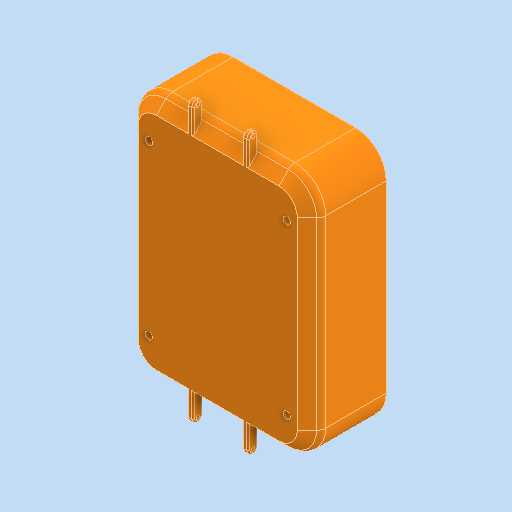
# Autodesk Inventor part: Cover Bawah
Saved by Autodesk Inventor 2026.2 (Build 302298010, 298A)
## iProperties
Created: 2026-05-23
Part Number: Cover Bawah
Material: PAEK Plastic
Document SubType Name: Modeling
Designer: HYLMI ATHA N
Density: 1.32 g/cm^3
Appearance: Orange
Author: HYLMI ATHA N
Autodesk Inventor part; units mm, degrees
(part 1 of 2)
ref_plane "XZ Plane" through (0, 0, 0) normal (0, 1, 0) x (-1, 0, 0)
ref_plane "XY Plane" through (0, 0, 0) normal (0, 0, 1) x (1, 0, 0)
sketch "Sketch2" plane through (0, 0, 0) normal (0, 0, 1) x (1, 0, 0)
  arc A0 (22.147, -28.6469) -> (23.335, -28.3619) centre (22.5, -27.5) ccw projected
  arc A1 (21.3819, -27.0644) -> (22.147, -28.6469) centre (21.59, -27.94) ccw projected
  arc A2 (23.6553, -27.1754) -> (21.3819, -27.0644) centre (22.5, -27.5) ccw projected
  arc A3 (25, -27.7096) -> (23.6553, -27.1754) centre (24.13, -27.94) ccw projected
  line L0 (25, -27.7096) -> (25, -25.6304) projected
  arc A4 (25, -25.1696) -> (25, -25.6304) centre (24.13, -25.4) ccw projected
  line L1 (25, -25.1696) -> (25, -23.0904) projected
  arc A5 (25, -22.6296) -> (25, -23.0904) centre (24.13, -22.86) ccw projected
  line L2 (25, -22.6296) -> (25, -20.5504) projected
  arc A6 (25, -20.0896) -> (25, -20.5504) centre (24.13, -20.32) ccw projected
  line L3 (25, -20.0896) -> (25, -18.0104) projected
  arc A7 (25, -17.5496) -> (25, -18.0104) centre (24.13, -17.78) ccw projected
  line L4 (25, -17.5496) -> (25, -15.4704) projected
  arc A8 (25, -15.0096) -> (25, -15.4704) centre (24.13, -15.24) ccw projected
  line L5 (25, -15.0096) -> (25, -12.9304) projected
  arc A9 (25, -12.4696) -> (25, -12.9304) centre (24.13, -12.7) ccw projected
  line L6 (25, -12.4696) -> (25, -10.3904) projected
  arc A10 (25, -9.9296) -> (25, -10.3904) centre (24.13, -10.16) ccw projected
  line L7 (25, -9.9296) -> (25, -7.8504) projected
  arc A11 (25, -7.3896) -> (25, -7.8504) centre (24.13, -7.62) ccw projected
  line L8 (25, -7.3896) -> (25, -5.3104) projected
  arc A12 (25, -4.8496) -> (25, -5.3104) centre (24.13, -5.08) ccw projected
  line L9 (25, -4.8496) -> (25, -2.7704) projected
  arc A13 (25, -2.3096) -> (25, -2.7704) centre (24.13, -2.54) ccw projected
  line L10 (25, -2.3096) -> (25, -0.2304) projected
  arc A14 (25, 0.2304) -> (25, -0.2304) centre (24.13, 0) ccw projected
  line L11 (25, 0.2304) -> (25, 2.3096) projected
  arc A15 (25, 2.7704) -> (25, 2.3096) centre (24.13, 2.54) ccw projected
  line L12 (25, 2.7704) -> (25, 4.8496) projected
  arc A16 (25, 5.3104) -> (25, 4.8496) centre (24.13, 5.08) ccw projected
  line L13 (25, 5.3104) -> (25, 7.3896) projected
  arc A17 (25, 7.8504) -> (25, 7.3896) centre (24.13, 7.62) ccw projected
  line L14 (25, 7.8504) -> (25, 9.9296) projected
  arc A18 (25, 10.3904) -> (25, 9.9296) centre (24.13, 10.16) ccw projected
  line L15 (25, 10.3904) -> (25, 12.4696) projected
  arc A19 (25, 12.9304) -> (25, 12.4696) centre (24.13, 12.7) ccw projected
  line L16 (25, 12.9304) -> (25, 15.0096) projected
  arc A20 (25, 15.4704) -> (25, 15.0096) centre (24.13, 15.24) ccw projected
  line L17 (25, 15.4704) -> (25, 17.5496) projected
  arc A21 (25, 18.0104) -> (25, 17.5496) centre (24.13, 17.78) ccw projected
  line L18 (25, 18.0104) -> (25, 20.0896) projected
  arc A22 (25, 20.5504) -> (25, 20.0896) centre (24.13, 20.32) ccw projected
  line L19 (25, 20.5504) -> (25, 22.6296) projected
  arc A23 (25, 23.0904) -> (25, 22.6296) centre (24.13, 22.86) ccw projected
  line L20 (25, 23.0904) -> (25, 25.1696) projected
  arc A24 (25, 25.6304) -> (25, 25.1696) centre (24.13, 25.4) ccw projected
  line L21 (25, 25.6304) -> (25, 27.7096) projected
  arc A25 (23.6553, 27.1754) -> (25, 27.7096) centre (24.13, 27.94) ccw projected
  arc A26 (21.3819, 27.0644) -> (23.6553, 27.1754) centre (22.5, 27.5) ccw projected
  arc A27 (22.147, 28.6469) -> (21.3819, 27.0644) centre (21.59, 27.94) ccw projected
  arc A28 (23.335, 28.3619) -> (22.147, 28.6469) centre (22.5, 27.5) ccw projected
  arc A29 (25, 28.1704) -> (23.335, 28.3619) centre (24.13, 27.94) ccw projected
  line L22 (25, 28.1704) -> (25, 30) projected
  line L23 (25, 30) -> (24.8913, 30) projected
  arc A30 (23.3687, 30) -> (24.8913, 30) centre (24.13, 30.48) ccw projected
  line L24 (23.3687, 30) -> (22.3513, 30) projected
  arc A31 (20.8287, 30) -> (22.3513, 30) centre (21.59, 30.48) ccw projected
  line L25 (20.8287, 30) -> (19.8113, 30) projected
  arc A32 (18.2887, 30) -> (19.8113, 30) centre (19.05, 30.48) ccw projected
  line L26 (18.2887, 30) -> (17.2713, 30) projected
  arc A33 (15.7487, 30) -> (17.2713, 30) centre (16.51, 30.48) ccw projected
  line L27 (15.7487, 30) -> (14.7313, 30) projected
  arc A34 (13.2087, 30) -> (14.7313, 30) centre (13.97, 30.48) ccw projected
  line L28 (13.2087, 30) -> (12.1913, 30) projected
  arc A35 (10.6687, 30) -> (12.1913, 30) centre (11.43, 30.48) ccw projected
  line L29 (10.6687, 30) -> (9.6513, 30) projected
  arc A36 (8.1287, 30) -> (9.6513, 30) centre (8.89, 30.48) ccw projected
  line L30 (8.1287, 30) -> (7.1113, 30) projected
  arc A37 (5.5887, 30) -> (7.1113, 30) centre (6.35, 30.48) ccw projected
  line L31 (5.5887, 30) -> (4.5713, 30) projected
  arc A38 (3.0487, 30) -> (4.5713, 30) centre (3.81, 30.48) ccw projected
  line L32 (3.0487, 30) -> (2.0313, 30) projected
  arc A39 (0.5087, 30) -> (2.0313, 30) centre (1.27, 30.48) ccw projected
  line L33 (0.5087, 30) -> (-0.5087, 30) projected
  arc A40 (-2.0313, 30) -> (-0.5087, 30) centre (-1.27, 30.48) ccw projected
  line L34 (-2.0313, 30) -> (-3.0487, 30) projected
  arc A41 (-4.5713, 30) -> (-3.0487, 30) centre (-3.81, 30.48) ccw projected
  line L35 (-4.5713, 30) -> (-5.5887, 30) projected
  arc A42 (-7.1113, 30) -> (-5.5887, 30) centre (-6.35, 30.48) ccw projected
  line L36 (-7.1113, 30) -> (-8.1287, 30) projected
  arc A43 (-9.6513, 30) -> (-8.1287, 30) centre (-8.89, 30.48) ccw projected
  line L37 (-9.6513, 30) -> (-10.6687, 30) projected
  arc A44 (-12.1913, 30) -> (-10.6687, 30) centre (-11.43, 30.48) ccw projected
  line L38 (-12.1913, 30) -> (-13.2087, 30) projected
  arc A45 (-14.7313, 30) -> (-13.2087, 30) centre (-13.97, 30.48) ccw projected
  line L39 (-14.7313, 30) -> (-15.7487, 30) projected
  arc A46 (-17.2713, 30) -> (-15.7487, 30) centre (-16.51, 30.48) ccw projected
  line L40 (-17.2713, 30) -> (-18.2887, 30) projected
  arc A47 (-19.8113, 30) -> (-18.2887, 30) centre (-19.05, 30.48) ccw projected
  line L41 (-19.8113, 30) -> (-20.8287, 30) projected
  arc A48 (-22.3513, 30) -> (-20.8287, 30) centre (-21.59, 30.48) ccw projected
  line L42 (-22.3513, 30) -> (-23.3687, 30) projected
  arc A49 (-24.8913, 30) -> (-23.3687, 30) centre (-24.13, 30.48) ccw projected
  line L43 (-24.8913, 30) -> (-25, 30) projected
  line L44 (-25, 30) -> (-25, 28.1704) projected
  arc A50 (-24.8913, 28.42) -> (-25, 28.1704) centre (-24.13, 27.94) ccw projected
  arc A51 (-23.335, 28.3619) -> (-24.8913, 28.42) centre (-24.13, 27.94) ccw projected
  arc A52 (-22.147, 28.6469) -> (-23.335, 28.3619) centre (-22.5, 27.5) ccw projected
  arc A53 (-21.3819, 27.0644) -> (-22.147, 28.6469) centre (-21.59, 27.94) ccw projected
  arc A54 (-23.6553, 27.1754) -> (-21.3819, 27.0644) centre (-22.5, 27.5) ccw projected
  arc A55 (-24.8913, 27.46) -> (-23.6553, 27.1754) centre (-24.13, 27.94) ccw projected
  arc A56 (-25, 27.7096) -> (-24.8913, 27.46) centre (-24.13, 27.94) ccw projected
  line L45 (-25, 27.7096) -> (-25, 25.6304) projected
  arc A57 (-24.8913, 25.88) -> (-25, 25.6304) centre (-24.13, 25.4) ccw projected
  arc A58 (-24.8913, 24.92) -> (-24.8913, 25.88) centre (-24.13, 25.4) ccw projected
  arc A59 (-25, 25.1696) -> (-24.8913, 24.92) centre (-24.13, 25.4) ccw projected
  line L46 (-25, 25.1696) -> (-25, 23.0904) projected
  arc A60 (-24.8913, 23.34) -> (-25, 23.0904) centre (-24.13, 22.86) ccw projected
  arc A61 (-24.8913, 22.38) -> (-24.8913, 23.34) centre (-24.13, 22.86) ccw projected
  arc A62 (-25, 22.6296) -> (-24.8913, 22.38) centre (-24.13, 22.86) ccw projected
  line L47 (-25, 22.6296) -> (-25, 20.5504) projected
  arc A63 (-24.8913, 20.8) -> (-25, 20.5504) centre (-24.13, 20.32) ccw projected
  arc A64 (-24.8913, 19.84) -> (-24.8913, 20.8) centre (-24.13, 20.32) ccw projected
  arc A65 (-25, 20.0896) -> (-24.8913, 19.84) centre (-24.13, 20.32) ccw projected
  line L48 (-25, 20.0896) -> (-25, 18.0104) projected
  arc A66 (-24.8913, 18.26) -> (-25, 18.0104) centre (-24.13, 17.78) ccw projected
  arc A67 (-24.8913, 17.3) -> (-24.8913, 18.26) centre (-24.13, 17.78) ccw projected
  arc A68 (-25, 17.5496) -> (-24.8913, 17.3) centre (-24.13, 17.78) ccw projected
  line L49 (-25, 17.5496) -> (-25, 15.4704) projected
  arc A69 (-24.8913, 15.72) -> (-25, 15.4704) centre (-24.13, 15.24) ccw projected
  arc A70 (-24.8913, 14.76) -> (-24.8913, 15.72) centre (-24.13, 15.24) ccw projected
  arc A71 (-25, 15.0096) -> (-24.8913, 14.76) centre (-24.13, 15.24) ccw projected
  line L50 (-25, 15.0096) -> (-25, 12.9304) projected
  arc A72 (-24.8913, 13.18) -> (-25, 12.9304) centre (-24.13, 12.7) ccw projected
  arc A73 (-24.8913, 12.22) -> (-24.8913, 13.18) centre (-24.13, 12.7) ccw projected
  arc A74 (-25, 12.4696) -> (-24.8913, 12.22) centre (-24.13, 12.7) ccw projected
  line L51 (-25, 12.4696) -> (-25, 10.3904) projected
  arc A75 (-24.8913, 10.64) -> (-25, 10.3904) centre (-24.13, 10.16) ccw projected
  arc A76 (-24.8913, 9.68) -> (-24.8913, 10.64) centre (-24.13, 10.16) ccw projected
  arc A77 (-25, 9.9296) -> (-24.8913, 9.68) centre (-24.13, 10.16) ccw projected
  line L52 (-25, 9.9296) -> (-25, 7.8504) projected
  arc A78 (-24.8913, 8.1) -> (-25, 7.8504) centre (-24.13, 7.62) ccw projected
  arc A79 (-24.8913, 7.14) -> (-24.8913, 8.1) centre (-24.13, 7.62) ccw projected
  arc A80 (-25, 7.3896) -> (-24.8913, 7.14) centre (-24.13, 7.62) ccw projected
  line L53 (-25, 7.3896) -> (-25, 5.3104) projected
  arc A81 (-24.8913, 5.56) -> (-25, 5.3104) centre (-24.13, 5.08) ccw projected
  arc A82 (-24.8913, 4.6) -> (-24.8913, 5.56) centre (-24.13, 5.08) ccw projected
  arc A83 (-25, 4.8496) -> (-24.8913, 4.6) centre (-24.13, 5.08) ccw projected
  line L54 (-25, 4.8496) -> (-25, 2.7704) projected
  arc A84 (-24.8913, 3.02) -> (-25, 2.7704) centre (-24.13, 2.54) ccw projected
  arc A85 (-24.8913, 2.06) -> (-24.8913, 3.02) centre (-24.13, 2.54) ccw projected
  arc A86 (-25, 2.3096) -> (-24.8913, 2.06) centre (-24.13, 2.54) ccw projected
  line L55 (-25, 2.3096) -> (-25, 0.2304) projected
  arc A87 (-24.8913, 0.48) -> (-25, 0.2304) centre (-24.13, 0) ccw projected
  arc A88 (-24.8913, -0.48) -> (-24.8913, 0.48) centre (-24.13, 0) ccw projected
  arc A89 (-25, -0.2304) -> (-24.8913, -0.48) centre (-24.13, 0) ccw projected
  line L56 (-25, -0.2304) -> (-25, -2.3096) projected
  arc A90 (-24.8913, -2.06) -> (-25, -2.3096) centre (-24.13, -2.54) ccw projected
  arc A91 (-24.8913, -3.02) -> (-24.8913, -2.06) centre (-24.13, -2.54) ccw projected
  arc A92 (-25, -2.7704) -> (-24.8913, -3.02) centre (-24.13, -2.54) ccw projected
  line L57 (-25, -2.7704) -> (-25, -4.8496) projected
  arc A93 (-24.8913, -4.6) -> (-25, -4.8496) centre (-24.13, -5.08) ccw projected
  arc A94 (-24.8913, -5.56) -> (-24.8913, -4.6) centre (-24.13, -5.08) ccw projected
  arc A95 (-25, -5.3104) -> (-24.8913, -5.56) centre (-24.13, -5.08) ccw projected
  line L58 (-25, -5.3104) -> (-25, -7.3896) projected
  arc A96 (-24.8913, -7.14) -> (-25, -7.3896) centre (-24.13, -7.62) ccw projected
  arc A97 (-24.8913, -8.1) -> (-24.8913, -7.14) centre (-24.13, -7.62) ccw projected
  arc A98 (-25, -7.8504) -> (-24.8913, -8.1) centre (-24.13, -7.62) ccw projected
  line L59 (-25, -7.8504) -> (-25, -9.9296) projected
  arc A99 (-24.8913, -9.68) -> (-25, -9.9296) centre (-24.13, -10.16) ccw projected
  arc A100 (-24.8913, -10.64) -> (-24.8913, -9.68) centre (-24.13, -10.16) ccw projected
  arc A101 (-25, -10.3904) -> (-24.8913, -10.64) centre (-24.13, -10.16) ccw projected
  line L60 (-25, -10.3904) -> (-25, -12.4696) projected
  arc A102 (-24.8913, -12.22) -> (-25, -12.4696) centre (-24.13, -12.7) ccw projected
  arc A103 (-24.8913, -13.18) -> (-24.8913, -12.22) centre (-24.13, -12.7) ccw projected
  arc A104 (-25, -12.9304) -> (-24.8913, -13.18) centre (-24.13, -12.7) ccw projected
  line L61 (-25, -12.9304) -> (-25, -15.0096) projected
  arc A105 (-24.8913, -14.76) -> (-25, -15.0096) centre (-24.13, -15.24) ccw projected
  arc A106 (-24.8913, -15.72) -> (-24.8913, -14.76) centre (-24.13, -15.24) ccw projected
  arc A107 (-25, -15.4704) -> (-24.8913, -15.72) centre (-24.13, -15.24) ccw projected
  line L62 (-25, -15.4704) -> (-25, -17.5496) projected
  arc A108 (-24.8913, -17.3) -> (-25, -17.5496) centre (-24.13, -17.78) ccw projected
  arc A109 (-24.8913, -18.26) -> (-24.8913, -17.3) centre (-24.13, -17.78) ccw projected
  arc A110 (-25, -18.0104) -> (-24.8913, -18.26) centre (-24.13, -17.78) ccw projected
  line L63 (-25, -18.0104) -> (-25, -20.0896) projected
  arc A111 (-24.8913, -19.84) -> (-25, -20.0896) centre (-24.13, -20.32) ccw projected
  arc A112 (-24.8913, -20.8) -> (-24.8913, -19.84) centre (-24.13, -20.32) ccw projected
  arc A113 (-25, -20.5504) -> (-24.8913, -20.8) centre (-24.13, -20.32) ccw projected
  line L64 (-25, -20.5504) -> (-25, -22.6296) projected
  arc A114 (-24.8913, -22.38) -> (-25, -22.6296) centre (-24.13, -22.86) ccw projected
  arc A115 (-24.8913, -23.34) -> (-24.8913, -22.38) centre (-24.13, -22.86) ccw projected
  arc A116 (-25, -23.0904) -> (-24.8913, -23.34) centre (-24.13, -22.86) ccw projected
  line L65 (-25, -23.0904) -> (-25, -25.1696) projected
  arc A117 (-24.8913, -24.92) -> (-25, -25.1696) centre (-24.13, -25.4) ccw projected
  arc A118 (-24.8913, -25.88) -> (-24.8913, -24.92) centre (-24.13, -25.4) ccw projected
  arc A119 (-25, -25.6304) -> (-24.8913, -25.88) centre (-24.13, -25.4) ccw projected
  line L66 (-25, -25.6304) -> (-25, -27.7096) projected
  arc A120 (-24.8913, -27.46) -> (-25, -27.7096) centre (-24.13, -27.94) ccw projected
  arc A121 (-23.6553, -27.1754) -> (-24.8913, -27.46) centre (-24.13, -27.94) ccw projected
  arc A122 (-21.3819, -27.0644) -> (-23.6553, -27.1754) centre (-22.5, -27.5) ccw projected
  arc A123 (-22.147, -28.6469) -> (-21.3819, -27.0644) centre (-21.59, -27.94) ccw projected
  arc A124 (-23.335, -28.3619) -> (-22.147, -28.6469) centre (-22.5, -27.5) ccw projected
  arc A125 (-24.8913, -28.42) -> (-23.335, -28.3619) centre (-24.13, -27.94) ccw projected
  arc A126 (-25, -28.1704) -> (-24.8913, -28.42) centre (-24.13, -27.94) ccw projected
  line L67 (-25, -28.1704) -> (-25, -30) projected
  line L68 (-25, -30) -> (-24.8913, -30) projected
  arc A127 (-23.3687, -30) -> (-24.8913, -30) centre (-24.13, -30.48) ccw projected
  line L69 (-23.3687, -30) -> (-22.3513, -30) projected
  arc A128 (-20.8287, -30) -> (-22.3513, -30) centre (-21.59, -30.48) ccw projected
  line L70 (-20.8287, -30) -> (-19.8113, -30) projected
  arc A129 (-18.2887, -30) -> (-19.8113, -30) centre (-19.05, -30.48) ccw projected
  line L71 (-18.2887, -30) -> (-17.2713, -30) projected
  arc A130 (-15.7487, -30) -> (-17.2713, -30) centre (-16.51, -30.48) ccw projected
  line L72 (-15.7487, -30) -> (-14.7313, -30) projected
  arc A131 (-13.2087, -30) -> (-14.7313, -30) centre (-13.97, -30.48) ccw projected
  line L73 (-13.2087, -30) -> (-12.1913, -30) projected
  arc A132 (-10.6687, -30) -> (-12.1913, -30) centre (-11.43, -30.48) ccw projected
  line L74 (-10.6687, -30) -> (-9.6513, -30) projected
  arc A133 (-8.1287, -30) -> (-9.6513, -30) centre (-8.89, -30.48) ccw projected
  line L75 (-8.1287, -30) -> (-7.1113, -30) projected
  arc A134 (-5.5887, -30) -> (-7.1113, -30) centre (-6.35, -30.48) ccw projected
  line L76 (-5.5887, -30) -> (-4.5713, -30) projected
  arc A135 (-3.0487, -30) -> (-4.5713, -30) centre (-3.81, -30.48) ccw projected
  line L77 (-3.0487, -30) -> (-2.0313, -30) projected
  arc A136 (-0.5087, -30) -> (-2.0313, -30) centre (-1.27, -30.48) ccw projected
  line L78 (-0.5087, -30) -> (0.5087, -30) projected
  arc A137 (2.0313, -30) -> (0.5087, -30) centre (1.27, -30.48) ccw projected
  line L79 (2.0313, -30) -> (3.0487, -30) projected
  arc A138 (4.5713, -30) -> (3.0487, -30) centre (3.81, -30.48) ccw projected
  line L80 (4.5713, -30) -> (5.5887, -30) projected
  arc A139 (7.1113, -30) -> (5.5887, -30) centre (6.35, -30.48) ccw projected
  line L81 (7.1113, -30) -> (8.1287, -30) projected
  arc A140 (9.6513, -30) -> (8.1287, -30) centre (8.89, -30.48) ccw projected
  line L82 (9.6513, -30) -> (10.6687, -30) projected
  arc A141 (12.1913, -30) -> (10.6687, -30) centre (11.43, -30.48) ccw projected
  line L83 (12.1913, -30) -> (13.2087, -30) projected
  arc A142 (14.7313, -30) -> (13.2087, -30) centre (13.97, -30.48) ccw projected
  line L84 (14.7313, -30) -> (15.7487, -30) projected
  arc A143 (17.2713, -30) -> (15.7487, -30) centre (16.51, -30.48) ccw projected
  line L85 (17.2713, -30) -> (18.2887, -30) projected
  arc A144 (19.8113, -30) -> (18.2887, -30) centre (19.05, -30.48) ccw projected
  line L86 (19.8113, -30) -> (20.8287, -30) projected
  arc A145 (22.3513, -30) -> (20.8287, -30) centre (21.59, -30.48) ccw projected
  line L87 (22.3513, -30) -> (23.3687, -30) projected
  arc A146 (24.8913, -30) -> (23.3687, -30) centre (24.13, -30.48) ccw projected
  line L88 (24.8913, -30) -> (25, -30) projected
  line L89 (25, -30) -> (25, -28.1704) projected
  arc A147 (23.335, -28.3619) -> (25, -28.1704) centre (24.13, -27.94) ccw projected
  circle A148 centre (1.27, 0) radius 0.9 projected
  circle A149 centre (1.27, 5.08) radius 0.9 projected
  circle A150 centre (1.27, 10.16) radius 0.9 projected
  circle A151 centre (1.27, 15.24) radius 0.9 projected
  circle A152 centre (1.27, 20.32) radius 0.9 projected
  circle A153 centre (1.27, 25.4) radius 0.9 projected
  circle A154 centre (3.81, 0) radius 0.9 projected
  circle A155 centre (3.81, 5.08) radius 0.9 projected
  circle A156 centre (3.81, 10.16) radius 0.9 projected
  circle A157 centre (3.81, 15.24) radius 0.9 projected
  circle A158 centre (3.81, 20.32) radius 0.9 projected
  circle A159 centre (3.81, 25.4) radius 0.9 projected
  circle A160 centre (6.35, 0) radius 0.9 projected
  circle A161 centre (6.35, 5.08) radius 0.9 projected
  circle A162 centre (6.35, 10.16) radius 0.9 projected
  circle A163 centre (6.35, 15.24) radius 0.9 projected
  circle A164 centre (6.35, 20.32) radius 0.9 projected
  circle A165 centre (6.35, 25.4) radius 0.9 projected
  circle A166 centre (8.89, 0) radius 0.9 projected
  circle A167 centre (8.89, 5.08) radius 0.9 projected
  circle A168 centre (8.89, 10.16) radius 0.9 projected
  circle A169 centre (8.89, 15.24) radius 0.9 projected
  circle A170 centre (8.89, 20.32) radius 0.9 projected
  circle A171 centre (8.89, 25.4) radius 0.9 projected
  circle A172 centre (11.43, 0) radius 0.9 projected
  circle A173 centre (11.43, 5.08) radius 0.9 projected
  circle A174 centre (11.43, 10.16) radius 0.9 projected
  circle A175 centre (11.43, 15.24) radius 0.9 projected
  circle A176 centre (11.43, 20.32) radius 0.9 projected
  circle A177 centre (11.43, 25.4) radius 0.9 projected
  circle A178 centre (13.97, 0) radius 0.9 projected
  circle A179 centre (13.97, 5.08) radius 0.9 projected
  circle A180 centre (13.97, 10.16) radius 0.9 projected
  circle A181 centre (13.97, 15.24) radius 0.9 projected
  circle A182 centre (13.97, 20.32) radius 0.9 projected
  circle A183 centre (13.97, 25.4) radius 0.9 projected
  circle A184 centre (16.51, 0) radius 0.9 projected
  circle A185 centre (16.51, 5.08) radius 0.9 projected
  circle A186 centre (16.51, 10.16) radius 0.9 projected
  circle A187 centre (16.51, 15.24) radius 0.9 projected
  circle A188 centre (16.51, 20.32) radius 0.9 projected
  circle A189 centre (16.51, 25.4) radius 0.9 projected
  circle A190 centre (19.05, 0) radius 0.9 projected
  circle A191 centre (19.05, 5.08) radius 0.9 projected
  circle A192 centre (19.05, 10.16) radius 0.9 projected
  circle A193 centre (19.05, 15.24) radius 0.9 projected
  circle A194 centre (19.05, 20.32) radius 0.9 projected
  circle A195 centre (19.05, 25.4) radius 0.9 projected
  circle A196 centre (21.59, 0) radius 0.9 projected
  circle A197 centre (21.59, 5.08) radius 0.9 projected
  circle A198 centre (21.59, 10.16) radius 0.9 projected
  circle A199 centre (21.59, 15.24) radius 0.9 projected
  circle A200 centre (21.59, 20.32) radius 0.9 projected
  circle A201 centre (21.59, 25.4) radius 0.9 projected
  circle A202 centre (1.27, -2.54) radius 0.9 projected
  circle A203 centre (1.27, -5.08) radius 0.9 projected
  circle A204 centre (1.27, -7.62) radius 0.9 projected
  circle A205 centre (1.27, -10.16) radius 0.9 projected
  circle A206 centre (1.27, -12.7) radius 0.9 projected
  circle A207 centre (1.27, -15.24) radius 0.9 projected
  circle A208 centre (1.27, -17.78) radius 0.9 projected
  circle A209 centre (1.27, -20.32) radius 0.9 projected
  circle A210 centre (1.27, -22.86) radius 0.9 projected
  circle A211 centre (1.27, -25.4) radius 0.9 projected
  circle A212 centre (1.27, -27.94) radius 0.9 projected
  circle A213 centre (3.81, -2.54) radius 0.9 projected
  circle A214 centre (3.81, -5.08) radius 0.9 projected
  circle A215 centre (3.81, -7.62) radius 0.9 projected
  circle A216 centre (3.81, -10.16) radius 0.9 projected
  circle A217 centre (3.81, -12.7) radius 0.9 projected
  circle A218 centre (3.81, -15.24) radius 0.9 projected
  circle A219 centre (3.81, -17.78) radius 0.9 projected
  circle A220 centre (3.81, -20.32) radius 0.9 projected
  circle A221 centre (3.81, -22.86) radius 0.9 projected
  circle A222 centre (3.81, -25.4) radius 0.9 projected
  circle A223 centre (3.81, -27.94) radius 0.9 projected
  circle A224 centre (6.35, -2.54) radius 0.9 projected
  circle A225 centre (6.35, -5.08) radius 0.9 projected
  circle A226 centre (6.35, -7.62) radius 0.9 projected
  circle A227 centre (6.35, -10.16) radius 0.9 projected
  circle A228 centre (6.35, -12.7) radius 0.9 projected
  circle A229 centre (6.35, -15.24) radius 0.9 projected
  circle A230 centre (6.35, -17.78) radius 0.9 projected
  circle A231 centre (6.35, -20.32) radius 0.9 projected
  circle A232 centre (6.35, -22.86) radius 0.9 projected
  circle A233 centre (6.35, -25.4) radius 0.9 projected
  circle A234 centre (6.35, -27.94) radius 0.9 projected
  circle A235 centre (8.89, -2.54) radius 0.9 projected
  circle A236 centre (8.89, -5.08) radius 0.9 projected
  circle A237 centre (8.89, -7.62) radius 0.9 projected
  circle A238 centre (8.89, -10.16) radius 0.9 projected
  circle A239 centre (8.89, -12.7) radius 0.9 projected
  circle A240 centre (8.89, -15.24) radius 0.9 projected
  circle A241 centre (8.89, -17.78) radius 0.9 projected
  circle A242 centre (8.89, -20.32) radius 0.9 projected
  circle A243 centre (8.89, -22.86) radius 0.9 projected
  circle A244 centre (8.89, -25.4) radius 0.9 projected
  circle A245 centre (8.89, -27.94) radius 0.9 projected
  circle A246 centre (11.43, -2.54) radius 0.9 projected
  circle A247 centre (11.43, -5.08) radius 0.9 projected
  circle A248 centre (11.43, -7.62) radius 0.9 projected
  circle A249 centre (11.43, -10.16) radius 0.9 projected
  circle A250 centre (11.43, -12.7) radius 0.9 projected
  circle A251 centre (11.43, -15.24) radius 0.9 projected
  circle A252 centre (11.43, -17.78) radius 0.9 projected
  circle A253 centre (11.43, -20.32) radius 0.9 projected
  circle A254 centre (11.43, -22.86) radius 0.9 projected
  circle A255 centre (11.43, -25.4) radius 0.9 projected
  circle A256 centre (11.43, -27.94) radius 0.9 projected
  circle A257 centre (13.97, -2.54) radius 0.9 projected
  circle A258 centre (13.97, -5.08) radius 0.9 projected
  circle A259 centre (13.97, -7.62) radius 0.9 projected
  circle A260 centre (13.97, -10.16) radius 0.9 projected
  circle A261 centre (13.97, -12.7) radius 0.9 projected
  circle A262 centre (13.97, -15.24) radius 0.9 projected
  circle A263 centre (13.97, -17.78) radius 0.9 projected
  circle A264 centre (13.97, -20.32) radius 0.9 projected
  circle A265 centre (13.97, -22.86) radius 0.9 projected
  circle A266 centre (13.97, -25.4) radius 0.9 projected
  circle A267 centre (13.97, -27.94) radius 0.9 projected
  circle A268 centre (16.51, -2.54) radius 0.9 projected
  circle A269 centre (16.51, -5.08) radius 0.9 projected
  circle A270 centre (16.51, -7.62) radius 0.9 projected
  circle A271 centre (16.51, -10.16) radius 0.9 projected
  circle A272 centre (16.51, -12.7) radius 0.9 projected
  circle A273 centre (16.51, -15.24) radius 0.9 projected
  circle A274 centre (16.51, -17.78) radius 0.9 projected
  circle A275 centre (16.51, -20.32) radius 0.9 projected
  circle A276 centre (16.51, -22.86) radius 0.9 projected
  circle A277 centre (16.51, -25.4) radius 0.9 projected
  circle A278 centre (16.51, -27.94) radius 0.9 projected
  circle A279 centre (19.05, -2.54) radius 0.9 projected
  circle A280 centre (19.05, -5.08) radius 0.9 projected
  circle A281 centre (19.05, -7.62) radius 0.9 projected
  circle A282 centre (19.05, -10.16) radius 0.9 projected
  circle A283 centre (19.05, -12.7) radius 0.9 projected
  circle A284 centre (19.05, -15.24) radius 0.9 projected
  circle A285 centre (19.05, -17.78) radius 0.9 projected
  circle A286 centre (19.05, -20.32) radius 0.9 projected
  circle A287 centre (19.05, -22.86) radius 0.9 projected
  circle A288 centre (19.05, -25.4) radius 0.9 projected
  circle A289 centre (19.05, -27.94) radius 0.9 projected
  circle A290 centre (21.59, -2.54) radius 0.9 projected
  circle A291 centre (21.59, -5.08) radius 0.9 projected
  circle A292 centre (21.59, -7.62) radius 0.9 projected
  circle A293 centre (21.59, -10.16) radius 0.9 projected
  circle A294 centre (21.59, -12.7) radius 0.9 projected
  circle A295 centre (21.59, -15.24) radius 0.9 projected
  circle A296 centre (21.59, -17.78) radius 0.9 projected
  circle A297 centre (21.59, -20.32) radius 0.9 projected
  circle A298 centre (21.59, -22.86) radius 0.9 projected
  circle A299 centre (21.59, -25.4) radius 0.9 projected
  circle A300 centre (-1.27, 0) radius 0.9 projected
  circle A301 centre (-1.27, 2.54) radius 0.9 projected
  circle A302 centre (-1.27, 5.08) radius 0.9 projected
  circle A303 centre (-1.27, 7.62) radius 0.9 projected
  circle A304 centre (-1.27, 10.16) radius 0.9 projected
  circle A305 centre (-1.27, 12.7) radius 0.9 projected
  circle A306 centre (-1.27, 15.24) radius 0.9 projected
  circle A307 centre (-1.27, 17.78) radius 0.9 projected
  circle A308 centre (-1.27, 20.32) radius 0.9 projected
  circle A309 centre (-1.27, 22.86) radius 0.9 projected
  circle A310 centre (-1.27, 25.4) radius 0.9 projected
  circle A311 centre (-1.27, 27.94) radius 0.9 projected
  circle A312 centre (-3.81, 0) radius 0.9 projected
  circle A313 centre (-3.81, 2.54) radius 0.9 projected
  circle A314 centre (-3.81, 5.08) radius 0.9 projected
  circle A315 centre (-3.81, 7.62) radius 0.9 projected
  circle A316 centre (-3.81, 10.16) radius 0.9 projected
  circle A317 centre (-3.81, 12.7) radius 0.9 projected
  circle A318 centre (-3.81, 15.24) radius 0.9 projected
  circle A319 centre (-3.81, 17.78) radius 0.9 projected
  circle A320 centre (-3.81, 20.32) radius 0.9 projected
  circle A321 centre (-3.81, 22.86) radius 0.9 projected
  circle A322 centre (-3.81, 25.4) radius 0.9 projected
  circle A323 centre (-3.81, 27.94) radius 0.9 projected
  circle A324 centre (-6.35, 0) radius 0.9 projected
  circle A325 centre (-6.35, 2.54) radius 0.9 projected
  circle A326 centre (-6.35, 5.08) radius 0.9 projected
  circle A327 centre (-6.35, 7.62) radius 0.9 projected
  circle A328 centre (-6.35, 10.16) radius 0.9 projected
  circle A329 centre (-6.35, 12.7) radius 0.9 projected
  circle A330 centre (-6.35, 15.24) radius 0.9 projected
  circle A331 centre (-6.35, 17.78) radius 0.9 projected
  circle A332 centre (-6.35, 20.32) radius 0.9 projected
  circle A333 centre (-6.35, 22.86) radius 0.9 projected
  circle A334 centre (-6.35, 25.4) radius 0.9 projected
  circle A335 centre (-6.35, 27.94) radius 0.9 projected
  circle A336 centre (-8.89, 0) radius 0.9 projected
  circle A337 centre (-8.89, 2.54) radius 0.9 projected
  circle A338 centre (-8.89, 5.08) radius 0.9 projected
  circle A339 centre (-8.89, 7.62) radius 0.9 projected
  circle A340 centre (-8.89, 10.16) radius 0.9 projected
  circle A341 centre (-8.89, 12.7) radius 0.9 projected
  circle A342 centre (-8.89, 15.24) radius 0.9 projected
  circle A343 centre (-8.89, 17.78) radius 0.9 projected
  circle A344 centre (-8.89, 20.32) radius 0.9 projected
  circle A345 centre (-8.89, 22.86) radius 0.9 projected
  circle A346 centre (-8.89, 25.4) radius 0.9 projected
  circle A347 centre (-8.89, 27.94) radius 0.9 projected
  circle A348 centre (-11.43, 0) radius 0.9 projected
  circle A349 centre (-11.43, 2.54) radius 0.9 projected
  circle A350 centre (-11.43, 5.08) radius 0.9 projected
  circle A351 centre (-11.43, 7.62) radius 0.9 projected
  circle A352 centre (-11.43, 10.16) radius 0.9 projected
  circle A353 centre (-11.43, 12.7) radius 0.9 projected
  circle A354 centre (-11.43, 15.24) radius 0.9 projected
  circle A355 centre (-11.43, 17.78) radius 0.9 projected
  circle A356 centre (-11.43, 20.32) radius 0.9 projected
  circle A357 centre (-11.43, 22.86) radius 0.9 projected
  circle A358 centre (-11.43, 25.4) radius 0.9 projected
  circle A359 centre (-11.43, 27.94) radius 0.9 projected
  circle A360 centre (-13.97, 0) radius 0.9 projected
  circle A361 centre (-13.97, 2.54) radius 0.9 projected
  circle A362 centre (-13.97, 5.08) radius 0.9 projected
  circle A363 centre (-13.97, 7.62) radius 0.9 projected
  circle A364 centre (-13.97, 10.16) radius 0.9 projected
  circle A365 centre (-13.97, 12.7) radius 0.9 projected
  circle A366 centre (-13.97, 15.24) radius 0.9 projected
  circle A367 centre (-13.97, 17.78) radius 0.9 projected
  circle A368 centre (-13.97, 20.32) radius 0.9 projected
  circle A369 centre (-13.97, 22.86) radius 0.9 projected
  circle A370 centre (-13.97, 25.4) radius 0.9 projected
  circle A371 centre (-13.97, 27.94) radius 0.9 projected
  circle A372 centre (-16.51, 0) radius 0.9 projected
  circle A373 centre (-16.51, 2.54) radius 0.9 projected
  circle A374 centre (-16.51, 5.08) radius 0.9 projected
  circle A375 centre (-16.51, 7.62) radius 0.9 projected
  circle A376 centre (-16.51, 10.16) radius 0.9 projected
  circle A377 centre (-16.51, 12.7) radius 0.9 projected
  circle A378 centre (-16.51, 15.24) radius 0.9 projected
  circle A379 centre (-16.51, 17.78) radius 0.9 projected
  circle A380 centre (-16.51, 20.32) radius 0.9 projected
  circle A381 centre (-16.51, 22.86) radius 0.9 projected
  circle A382 centre (-16.51, 25.4) radius 0.9 projected
  circle A383 centre (-16.51, 27.94) radius 0.9 projected
  circle A384 centre (-19.05, 0) radius 0.9 projected
  circle A385 centre (-19.05, 2.54) radius 0.9 projected
  circle A386 centre (-19.05, 5.08) radius 0.9 projected
  circle A387 centre (-19.05, 7.62) radius 0.9 projected
  circle A388 centre (-19.05, 10.16) radius 0.9 projected
  circle A389 centre (-19.05, 12.7) radius 0.9 projected
  circle A390 centre (-19.05, 15.24) radius 0.9 projected
  circle A391 centre (-19.05, 17.78) radius 0.9 projected
  circle A392 centre (-19.05, 20.32) radius 0.9 projected
  circle A393 centre (-19.05, 22.86) radius 0.9 projected
  circle A394 centre (-19.05, 25.4) radius 0.9 projected
  circle A395 centre (-19.05, 27.94) radius 0.9 projected
  circle A396 centre (-21.59, 0) radius 0.9 projected
  circle A397 centre (-21.59, 2.54) radius 0.9 projected
  circle A398 centre (-21.59, 5.08) radius 0.9 projected
  circle A399 centre (-21.59, 7.62) radius 0.9 projected
  circle A400 centre (-21.59, 10.16) radius 0.9 projected
  circle A401 centre (-21.59, 12.7) radius 0.9 projected
  circle A402 centre (-21.59, 15.24) radius 0.9 projected
  circle A403 centre (-21.59, 17.78) radius 0.9 projected
  circle A404 centre (-21.59, 20.32) radius 0.9 projected
  circle A405 centre (-21.59, 22.86) radius 0.9 projected
  circle A406 centre (-21.59, 25.4) radius 0.9 projected
  circle A407 centre (-1.27, -2.54) radius 0.9 projected
  circle A408 centre (-1.27, -7.62) radius 0.9 projected
  circle A409 centre (-1.27, -12.7) radius 0.9 projected
  circle A410 centre (-1.27, -17.78) radius 0.9 projected
  circle A411 centre (-1.27, -22.86) radius 0.9 projected
  circle A412 centre (-1.27, -27.94) radius 0.9 projected
  circle A413 centre (-3.81, -5.08) radius 0.9 projected
  circle A414 centre (-3.81, -10.16) radius 0.9 projected
  circle A415 centre (-3.81, -15.24) radius 0.9 projected
  circle A416 centre (-3.81, -20.32) radius 0.9 projected
  circle A417 centre (-3.81, -25.4) radius 0.9 projected
  circle A418 centre (-6.35, -2.54) radius 0.9 projected
  circle A419 centre (-6.35, -7.62) radius 0.9 projected
  circle A420 centre (-6.35, -12.7) radius 0.9 projected
  circle A421 centre (-6.35, -17.78) radius 0.9 projected
  circle A422 centre (-6.35, -22.86) radius 0.9 projected
  circle A423 centre (-6.35, -27.94) radius 0.9 projected
  circle A424 centre (-8.89, -5.08) radius 0.9 projected
  circle A425 centre (-8.89, -10.16) radius 0.9 projected
  circle A426 centre (-8.89, -15.24) radius 0.9 projected
  circle A427 centre (-8.89, -20.32) radius 0.9 projected
  circle A428 centre (-8.89, -25.4) radius 0.9 projected
  circle A429 centre (-11.43, -2.54) radius 0.9 projected
  circle A430 centre (-11.43, -7.62) radius 0.9 projected
  circle A431 centre (-11.43, -12.7) radius 0.9 projected
  circle A432 centre (-11.43, -17.78) radius 0.9 projected
  circle A433 centre (-11.43, -22.86) radius 0.9 projected
  circle A434 centre (-11.43, -27.94) radius 0.9 projected
  circle A435 centre (-13.97, -5.08) radius 0.9 projected
  circle A436 centre (-13.97, -10.16) radius 0.9 projected
  circle A437 centre (-13.97, -15.24) radius 0.9 projected
  circle A438 centre (-13.97, -20.32) radius 0.9 projected
  circle A439 centre (-13.97, -25.4) radius 0.9 projected
  circle A440 centre (-16.51, -2.54) radius 0.9 projected
  circle A441 centre (-16.51, -7.62) radius 0.9 projected
  circle A442 centre (-16.51, -12.7) radius 0.9 projected
  circle A443 centre (-16.51, -17.78) radius 0.9 projected
  circle A444 centre (-16.51, -22.86) radius 0.9 projected
  circle A445 centre (-16.51, -27.94) radius 0.9 projected
  circle A446 centre (-19.05, -5.08) radius 0.9 projected
  circle A447 centre (-19.05, -10.16) radius 0.9 projected
  circle A448 centre (-19.05, -15.24) radius 0.9 projected
  circle A449 centre (-19.05, -20.32) radius 0.9 projected
  circle A450 centre (-19.05, -25.4) radius 0.9 projected
  circle A451 centre (-21.59, -2.54) radius 0.9 projected
  circle A452 centre (-21.59, -7.62) radius 0.9 projected
  circle A453 centre (-21.59, -12.7) radius 0.9 projected
  circle A454 centre (-21.59, -17.78) radius 0.9 projected
  circle A455 centre (-21.59, -22.86) radius 0.9 projected
  circle A456 centre (-21.59, -25.4) radius 0.9 projected
  circle A457 centre (-21.59, -20.32) radius 0.9 projected
  circle A458 centre (-21.59, -15.24) radius 0.9 projected
  circle A459 centre (-21.59, -10.16) radius 0.9 projected
  circle A460 centre (-21.59, -5.08) radius 0.9 projected
  circle A461 centre (-19.05, -27.94) radius 0.9 projected
  circle A462 centre (-19.05, -22.86) radius 0.9 projected
  circle A463 centre (-19.05, -17.78) radius 0.9 projected
  circle A464 centre (-19.05, -12.7) radius 0.9 projected
  circle A465 centre (-19.05, -7.62) radius 0.9 projected
  circle A466 centre (-19.05, -2.54) radius 0.9 projected
  circle A467 centre (-16.51, -25.4) radius 0.9 projected
  circle A468 centre (-16.51, -20.32) radius 0.9 projected
  circle A469 centre (-16.51, -15.24) radius 0.9 projected
  circle A470 centre (-16.51, -10.16) radius 0.9 projected
  circle A471 centre (-16.51, -5.08) radius 0.9 projected
  circle A472 centre (-13.97, -27.94) radius 0.9 projected
  circle A473 centre (-13.97, -22.86) radius 0.9 projected
  circle A474 centre (-13.97, -17.78) radius 0.9 projected
  circle A475 centre (-13.97, -12.7) radius 0.9 projected
  circle A476 centre (-13.97, -7.62) radius 0.9 projected
  circle A477 centre (-13.97, -2.54) radius 0.9 projected
  circle A478 centre (-11.43, -25.4) radius 0.9 projected
  circle A479 centre (-11.43, -20.32) radius 0.9 projected
  circle A480 centre (-11.43, -15.24) radius 0.9 projected
  circle A481 centre (-11.43, -10.16) radius 0.9 projected
  circle A482 centre (-11.43, -5.08) radius 0.9 projected
  circle A483 centre (-8.89, -27.94) radius 0.9 projected
  circle A484 centre (-8.89, -22.86) radius 0.9 projected
  circle A485 centre (-8.89, -17.78) radius 0.9 projected
  circle A486 centre (-8.89, -12.7) radius 0.9 projected
  circle A487 centre (-8.89, -7.62) radius 0.9 projected
  circle A488 centre (-8.89, -2.54) radius 0.9 projected
  circle A489 centre (-6.35, -25.4) radius 0.9 projected
  circle A490 centre (-6.35, -20.32) radius 0.9 projected
  circle A491 centre (-6.35, -15.24) radius 0.9 projected
  circle A492 centre (-6.35, -10.16) radius 0.9 projected
  circle A493 centre (-6.35, -5.08) radius 0.9 projected
  circle A494 centre (-3.81, -27.94) radius 0.9 projected
  circle A495 centre (-3.81, -22.86) radius 0.9 projected
  circle A496 centre (-3.81, -17.78) radius 0.9 projected
  circle A497 centre (-3.81, -12.7) radius 0.9 projected
  circle A498 centre (-3.81, -7.62) radius 0.9 projected
  circle A499 centre (-3.81, -2.54) radius 0.9 projected
  circle A500 centre (-1.27, -25.4) radius 0.9 projected
  circle A501 centre (-1.27, -20.32) radius 0.9 projected
  circle A502 centre (-1.27, -15.24) radius 0.9 projected
  circle A503 centre (-1.27, -10.16) radius 0.9 projected
  circle A504 centre (-1.27, -5.08) radius 0.9 projected
  circle A505 centre (21.59, 22.86) radius 0.9 projected
  circle A506 centre (21.59, 17.78) radius 0.9 projected
  circle A507 centre (21.59, 12.7) radius 0.9 projected
  circle A508 centre (21.59, 7.62) radius 0.9 projected
  circle A509 centre (21.59, 2.54) radius 0.9 projected
  circle A510 centre (19.05, 27.94) radius 0.9 projected
  circle A511 centre (19.05, 22.86) radius 0.9 projected
  circle A512 centre (19.05, 17.78) radius 0.9 projected
  circle A513 centre (19.05, 12.7) radius 0.9 projected
  circle A514 centre (19.05, 7.62) radius 0.9 projected
  circle A515 centre (19.05, 2.54) radius 0.9 projected
  circle A516 centre (16.51, 27.94) radius 0.9 projected
  circle A517 centre (16.51, 22.86) radius 0.9 projected
  circle A518 centre (16.51, 17.78) radius 0.9 projected
  circle A519 centre (16.51, 12.7) radius 0.9 projected
  circle A520 centre (16.51, 7.62) radius 0.9 projected
  circle A521 centre (16.51, 2.54) radius 0.9 projected
  circle A522 centre (13.97, 27.94) radius 0.9 projected
  circle A523 centre (13.97, 22.86) radius 0.9 projected
  circle A524 centre (13.97, 17.78) radius 0.9 projected
  circle A525 centre (13.97, 12.7) radius 0.9 projected
  circle A526 centre (13.97, 7.62) radius 0.9 projected
  circle A527 centre (13.97, 2.54) radius 0.9 projected
  circle A528 centre (11.43, 27.94) radius 0.9 projected
  circle A529 centre (11.43, 22.86) radius 0.9 projected
  circle A530 centre (11.43, 17.78) radius 0.9 projected
  circle A531 centre (11.43, 12.7) radius 0.9 projected
  circle A532 centre (11.43, 7.62) radius 0.9 projected
  circle A533 centre (11.43, 2.54) radius 0.9 projected
  circle A534 centre (8.89, 27.94) radius 0.9 projected
  circle A535 centre (8.89, 22.86) radius 0.9 projected
  circle A536 centre (8.89, 17.78) radius 0.9 projected
  circle A537 centre (8.89, 12.7) radius 0.9 projected
  circle A538 centre (8.89, 7.62) radius 0.9 projected
  circle A539 centre (8.89, 2.54) radius 0.9 projected
  circle A540 centre (6.35, 27.94) radius 0.9 projected
  circle A541 centre (6.35, 22.86) radius 0.9 projected
  circle A542 centre (6.35, 17.78) radius 0.9 projected
  circle A543 centre (6.35, 12.7) radius 0.9 projected
  circle A544 centre (6.35, 7.62) radius 0.9 projected
  circle A545 centre (6.35, 2.54) radius 0.9 projected
  circle A546 centre (3.81, 27.94) radius 0.9 projected
  circle A547 centre (3.81, 22.86) radius 0.9 projected
  circle A548 centre (3.81, 17.78) radius 0.9 projected
  circle A549 centre (3.81, 12.7) radius 0.9 projected
  circle A550 centre (3.81, 7.62) radius 0.9 projected
  circle A551 centre (3.81, 2.54) radius 0.9 projected
  circle A552 centre (1.27, 27.94) radius 0.9 projected
  circle A553 centre (1.27, 22.86) radius 0.9 projected
  circle A554 centre (1.27, 17.78) radius 0.9 projected
  circle A555 centre (1.27, 12.7) radius 0.9 projected
  circle A556 centre (1.27, 7.62) radius 0.9 projected
  circle A557 centre (1.27, 2.54) radius 0.9 projected
  circle A558 centre (-22.5, -27.5) radius 1.2
  circle A559 centre (-22.5, 27.5) radius 1.2
  circle A560 centre (22.5, 27.5) radius 1.2
  circle A561 centre (22.5, -27.5) radius 1.2
  circle A562 centre (22.5, -27.5) radius 2.2
  circle A563 centre (-22.5, -27.5) radius 2.2
  circle A564 centre (-22.5, 27.5) radius 2.2
  circle A565 centre (22.5, 27.5) radius 2.2
  point P0 (0, 0)
  dimension "d0" = 2.4
  dimension "d1" = 2.4
  dimension "d2" = 2.4
  dimension "d3" = 2.4
  dimension "d4" = 1
  dimension "d5" = 1
  dimension "d6" = 1
  dimension "d7" = 1
  constraints: 8 centre point, 4 coincident
  measures "d0" diameter of A558
  measures "d1" diameter of A559
  measures "d2" diameter of A560
  measures "d3" diameter of A561
  measures "d4" radial gap between concentric circles of A561 A562
  measures "d5" radial gap between concentric circles of A558 A563
  measures "d6" radial gap between concentric circles of A559 A564
  measures "d7" radial gap between concentric circles of A560 A565
extrude "Extrusion1" add sketch "Sketch2" along normal blind 10 contours A0 A147 A562 A299 A4 A3 A2 A1 | A1 A561 | A561 A3 A562 A147 | A562 A299 | A4 A562 | A565 A201 A29 A28 A27 A26 A25 A24 | A24 A565 | A565 A201 | A563 A121 A558 A125 | A125 A124 A123 A122 A121 A563 A118 A456 | A25 A560 A29 A565 | A558 A123 | A563 A118 | A456 A563 | A27 A560 | A564 A406 A58 A55 A54 A53 A52 A51 | A51 A559 A55 A564 | A53 A559 | A564 A406 | A58 A564 picked at (21.518, -25.8242) picked at (21.518, 25.8242) picked at (-21.5036, -25.8254) picked at (-21.5036, 25.8254)
sketch "Sketch3" plane through (-22.5, 27.5, 10) normal (0, 0, 1) x (1, 0, 0)
  circle A0 centre (45, 0) radius 1.2 projected
  circle A1 centre (0, 0) radius 1.2 projected
  circle A2 centre (0, -55) radius 1.2 projected
  circle A3 centre (45, -55) radius 1.2 projected
  line L0 (45, 0) -> (0, -55)
  line L1 (0, -55) -> (0, 0)
  line L2 (0, 0) -> (45, -55)
  line L3 (-7.5, 12.5) -> (52.5, 12.5)
  line L4 (52.5, 12.5) -> (52.5, -67.5)
  line L5 (52.5, -67.5) -> (-7.5, -67.5)
  line L6 (-7.5, -67.5) -> (-7.5, 12.5)
  line L7 (-7.5, 12.5) -> (52.5, -67.5) construction
  line L8 (52.5, 12.5) -> (-7.5, -67.5) construction
  point P0 (22.5, -27.5)
  point P1 (47.3913, 2.5)
  point P2 (47.3913, -57.5)
  dimension "d10" = 80
  dimension "d11" = 60
  constraints: 18 end point, 2 midpoint, 2 parallel, 1 horizontal, 1 perpendicular, 1 vertical, 2 other
  measures "d10" distance of L3.end L4.end
  measures "d11" distance of L4.end L5.end
extrude "Extrusion2" add sketch "Sketch3" along normal blind 5 contours A1 L2 L0 A2 L1 | L3 L4 L5 L6
fillet "Fillet1" radius 10 4 edges at (30, 40, 12.5) (-30, 40, 12.5) (30, -40, 12.5) (-30, -40, 12.5)
sketch "Sketch4" plane through (-22.5, 27.5, 10) normal (0, 0, -1) x (-1, 0, 0)
  circle A0 centre (0, -55) radius 2.2 projected
  circle A1 centre (-45, -55) radius 2.2 projected
  circle A2 centre (0, 0) radius 2.2 projected
  circle A3 centre (-45, 0) radius 2.2 projected
  arc A4 (-2.5, -67.5) -> (7.5, -57.5) centre (-2.5, -57.5) ccw projected
  line L0 (7.5, 2.5) -> (7.5, -57.5) projected
  arc A5 (7.5, 2.5) -> (-2.5, 12.5) centre (-2.5, 2.5) ccw projected
  line L1 (-42.5, 12.5) -> (-2.5, 12.5) projected
  arc A6 (-42.5, 12.5) -> (-52.5, 2.5) centre (-42.5, 2.5) ccw projected
  line L2 (-52.5, -57.5) -> (-52.5, 2.5) projected
  arc A7 (-52.5, -57.5) -> (-42.5, -67.5) centre (-42.5, -57.5) ccw projected
  line L3 (-2.5, -67.5) -> (-42.5, -67.5) projected
  arc A8 (4.5, 2.5) -> (-2.5, 9.5) centre (-2.5, 2.5) ccw
  line L4 (4.5, 2.5) -> (4.5, -57.5)
  arc A9 (-2.5, -64.5) -> (4.5, -57.5) centre (-2.5, -57.5) ccw
  line L5 (-2.5, -64.5) -> (-42.5, -64.5)
  arc A10 (-49.5, -57.5) -> (-42.5, -64.5) centre (-42.5, -57.5) ccw
  line L6 (-49.5, -57.5) -> (-49.5, 2.5)
  arc A11 (-42.5, 9.5) -> (-49.5, 2.5) centre (-42.5, 2.5) ccw
  line L7 (-42.5, 9.5) -> (-2.5, 9.5)
  point P0 (-22.5, -27.5)
  dimension "d15" = 3
  constraints: 8 end point, 8 point on circle, 4 centre point, 7 other
  measures "d15" distance between parallel lines of L1 L7
extrude "Extrusion3" add sketch "Sketch4" along normal blind 20 contours L3 A7 L2 A6 L1 A5 L0 A4
chamfer "Chamfer1" distance 4 angle 45 8 edges at (30, 0, 15) (27.0711, 37.0711, 15) (0, 40, 15) (-27.0711, 37.0711, 15) (-30, 0, 15) (-27.0711, -37.0711, 15) (0, -40, 15) (27.0711, -37.0711, 15)
fillet "Fillet2" radius 3 8 edges at (27.0711, 37.0711, 11) (0, 40, 11) (-27.0711, 37.0711, 11) (-30, 0, 11) (-27.0711, -37.0711, 11) (0, -40, 11) (27.0711, -37.0711, 11) (30, 0, 11)
sketch "Sketch5" plane through (-20, -40, -10) normal (0, -1, 0) x (1, 0, 0)
  line L0 (0, 19.7574) -> (40, 19.7574) projected
  line L1 (0, 19.7574) -> (0, 0) projected
  line L2 (40, 0) -> (0, 0) projected
  line L3 (40, 19.7574) -> (40, 0) projected
  line L4 (35, 16.5) -> (5, 16.5)
  line L5 (5, 16.5) -> (5, 3.5)
  line L6 (5, 3.5) -> (35, 3.5)
  line L7 (35, 3.5) -> (35, 16.5)
  line L8 (35, 16.5) -> (5, 3.5) construction
  line L9 (5, 16.5) -> (35, 3.5) construction
  point P0 (20, 10)
  dimension "d22" = 30
  dimension "d23" = 13
  constraints: 12 end point, 2 midpoint, 2 parallel, 1 horizontal, 1 perpendicular
  measures "d22" distance of L6.end L5.end
  measures "d23" distance of L5.end L4.end
extrude "Extrusion4" add sketch "Sketch5" along normal blind 4 contours L7 L6 L5 L4
fillet "Fillet3" radius 3 4 edges at (15, -42, -6.5) (15, -42, 6.5) (-15, -42, -6.5) (-15, -42, 6.5)
fillet "Fillet4" radius 1 16 edges at (-14.1213, -40, -5.6213) (-15, -40, 0) (-14.1213, -40, 5.6213) (0, -40, 6.5) (14.1213, -40, 5.6213) (15, -40, 0) (14.1213, -40, -5.6213) (0, -40, -6.5) (14.1213, -44, -5.6213) (15, -44, 0) (14.1213, -44, 5.6213) (0, -44, 6.5) (-14.1213, -44, 5.6213) (-15, -44, 0) (-14.1213, -44, -5.6213) (0, -44, -6.5)